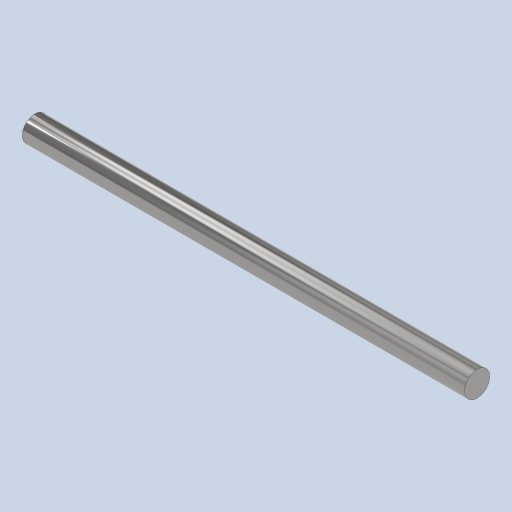
# Autodesk Inventor part: Eixo (rebite)
Saved by Autodesk Inventor 2024.3 (Build 283343000, 343)
## iProperties
Created: 2025-01-03
Part Number: Eixo (rebite)
Material: Alumínio 6061
Document SubType Name: Modeling
Designer: Cliente
Density: 2.7 g/cm^3
Appearance: Aço - Polido
Mass: 0.51301 g
Surface Area: 3.2572 cm^2
Volume: 0.190004 cm^3
Author: Cliente
Autodesk Inventor part; units mm, degrees
ref_plane "YZ Plane" through (0, 0, 0) normal (1, 0, 0) x (0, 1, 0)
ref_plane "XZ Plane" through (0, 0, 0) normal (0, 1, 0) x (-1, 0, 0)
ref_plane "XY Plane" through (0, 0, 0) normal (0, 0, 1) x (1, 0, 0)
sketch "Esboço1" plane through (0, 0, 0) normal (0, 0, 1) x (1, 0, 0)
  line L0 (21, -1.2) -> (-21, -1.2)
  line L1 (-21, -1.2) -> (-21, 1.2)
  line L2 (-21, 1.2) -> (21, 1.2)
  line L3 (21, 1.2) -> (21, -1.2)
  line L4 (21, -1.2) -> (-21, 1.2) construction
  line L5 (-21, -1.2) -> (21, 1.2) construction
  line L6 (-21, 0) -> (21, 0)
  point P0 (0, 0)
  dimension "d0" = 42
  dimension "d1" = 2.4
  constraints: 14 end point, 4 midpoint, 2 parallel, 1 horizontal, 1 perpendicular
  measures "d0" distance of L1.end L2.end
  measures "d1" distance of L0.end L1.end
revolve "Revolução1" add sketch "Esboço1" angle 360 about axis through (-21, 0, 0) along (1, 0, 0) contours L0 L1 L6 L3
